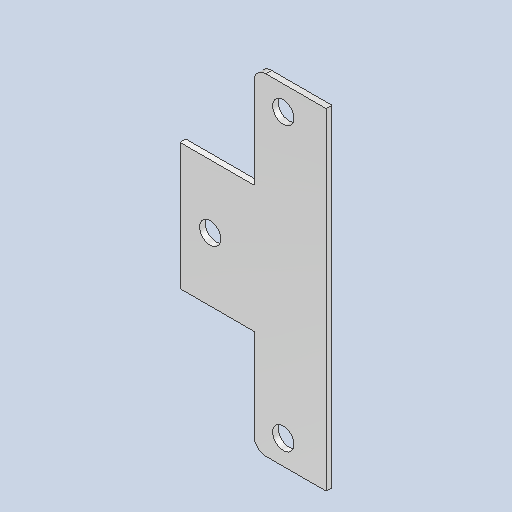
# Autodesk Inventor part: DMF-1217 Slot Plate Large 03
Saved by Autodesk Inventor 2026.2 (Build 302298000, 298)
## iProperties
Created: 2024-04-30
Part Number: DMF-1217 Slot Plate Large 03
Material: Stainless Steel AISI 304
Document SubType Name: Sheet Metal
Designer: admin
Stock Number: DMF-1217
Mass: 30.2951 g
Surface Area: 223.238 cm^2
Volume: 30.2951 cm^3
Density: 8 g/cm^3
Flat Pattern Width: 7.5 cm
Flat Pattern Length: 17 cm
Flat Pattern Area: 127.5 cm^2
Sheet Metal Rule: Default
Sheet Metal Width: 75,000 mm
Sheet Metal Length: 170,000 mm
Sheet Metal Area: 12750,000 mm^2
Appearance: Chrome - Satin
Author: pokla
Autodesk Inventor part; units mm, degrees
ref_plane "YZ Plane" through (0, 0, 0) normal (1, 0, 0) x (0, 1, 0)
ref_plane "XZ Plane" through (0, 0, 0) normal (0, 1, 0) x (-1, 0, 0)
ref_plane "XY Plane" through (0, 0, 0) normal (0, 0, 1) x (1, 0, 0)
sketch "Sketch1" plane through (0, 0, 0) normal (0, 0, 1) x (1, 0, 0)
  line L0 (0, 85) -> (0, -85)
  line L1 (0, -85) -> (-37, -85)
  line L2 (-37, -85) -> (-37, -32.5)
  line L3 (-37, -32.5) -> (-75, -32.5)
  line L4 (-75, -32.5) -> (-75, 32.5)
  line L5 (-75, 32.5) -> (-37, 32.5)
  line L6 (-37, 32.5) -> (-37, 85)
  line L7 (-37, 85) -> (0, 85)
  line L8 (-75, 0) -> (0, 0) construction
  dimension "d106" = 37
  dimension "d107" = 170
  dimension "d108" = 75
  dimension "d109" = 65
  measures "d106" distance of L0.end L1.end
  measures "d107" distance of L0.start L0.end
  measures "d108" distance between parallel lines of L0 L4
  measures "d109" distance of L3.end L4.end
extrude "Plate1" add sketch "Sketch1" along normal mid plane 3
fillet "Corner Round2" radius 6 2 edges at (-37, -85, 0) (-37, 85, 0)
sketch "Sketch8" plane through (0, 0, -1.5) normal (0, 0, -1) x (-1, 0, 0)
  circle A0 centre (59.5, 0) radius 5.5
  circle A1 centre (22, -72.5) radius 5.5
  circle A2 centre (22, 72.5) radius 5.5
  line L0 (59.5, 0) -> (0, 0) construction
  dimension "d110" = 59.5
  dimension "d111" = 145
  dimension "d112" = 22
  dimension "d113" = 11
  constraints: 3 centre point, 2 coincident, 2 end point, 1 equal radius, 1 horizontal, 1 other
  measures "d110" distance of point (0, 0) L0.start
  measures "d111" distance of A2.centre A1.centre
  measures "d112" horizontal distance of A2.centre point (0, 0)
  measures "d113" diameter of A0
extrude "Cut2" cut sketch "Sketch8" against normal blind 3
equation "\"d15\" = Thickness"
equation "\"BendRadius\" = Thickness"
equation "\"BendReliefWidth\" = Thickness"
equation "\"BendReliefDepth\" = 0.5 * Thickness"
equation "\"CornerReliefSize\" = 4 * Thickness"
equation "\"MinimumRemnant\" = 2 * Thickness"
equation "\"TransitionRadius\" = BendRadius"
equation "\"JacobiRadiusSize\" = BendRadius"
equation "\"GapSize\" = Thickness"
equation "\"Thickness\" = 3"
body "Solid1"
